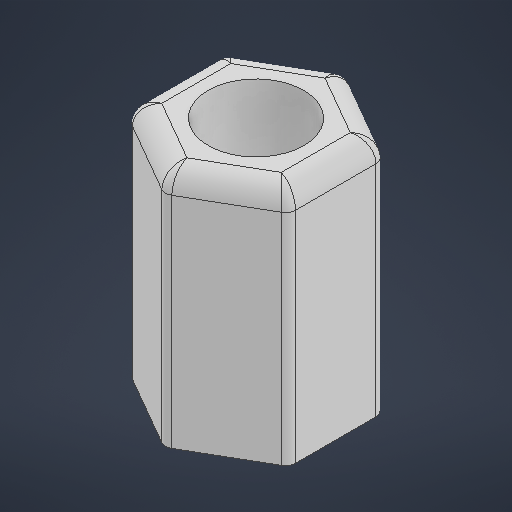
# Autodesk Inventor part: Гайка_М4
Saved by Autodesk Inventor 2026 (Build 300175050, 175E)
## iProperties
Created: 2026-11-05
Part Number: Гайка_М4
Material: Типовые
Document SubType Name: Modeling
Designer: VK7
Density: 1 g/cm^3
Appearance: По умолчанию
Author: VK7
## iProperties of the stored document Гайка_М5_3DПЕЧАТЬ.ipt
Created: 2026-11-05
Part Number: Гайка_М5_3DПЕЧАТЬ
Material: Типовые
Document SubType Name: Modeling
Designer: VK7
Density: 1 g/cm^3
Appearance: По умолчанию
Author: VK7
Autodesk Inventor part; units mm, degrees
ref_plane "YZ Plane" through (0, 0, 0) normal (1, 0, 0) x (0, 1, 0)
ref_plane "XZ Plane" through (0, 0, 0) normal (0, 1, 0) x (-1, 0, 0)
ref_plane "XY Plane" through (0, 0, 0) normal (0, 0, 1) x (1, 0, 0)
sketch "Эскиз1" plane through (0, 0, 0) normal (0, 1, 0) x (-1, 0, 0)
  line L0 (0, 0) -> (4, 0)
  line L1 (4, 0) -> (4, 3)
  line L2 (4, 3) -> (4, -3)
  line L3 (-0.5981, 4.9641) -> (4.5981, 1.9641)
  line L4 (-4.5981, 1.9641) -> (0.5981, 4.9641)
  line L5 (-4, -3) -> (-4, 3)
  line L6 (0.5981, -4.9641) -> (-4.5981, -1.9641)
  line L7 (4.5981, -1.9641) -> (-0.5981, -4.9641)
  circle A0 centre (0, 0) radius 2.4
  point P0 (4, 2.3094)
  point P1 (0, 4.6188)
  point P2 (-4, 2.3094)
  point P3 (-4, -2.3094)
  point P4 (0, -4.6188)
  point P5 (4, -2.3094)
  dimension "d0" = 4
  dimension "d1" = 3
  dimension "d2" = 6
  dimension "d5" = 360
  dimension "d7" = 4.8
  constraints: 16 end point, 1 centre point, 1 coincident, 1 horizontal, 1 perpendicular, 1 point on line, 19 other
  measures "d0" distance of L0.start L0.end
  measures "d1" distance of L0.end L1.end
  measures "d2" distance of L1.end L2.end
  measures "d7" diameter of A0
extrude "Выдавливание1" add sketch "Эскиз1" along normal blind 12
fillet "Сопряжение1" radius 0.5 6 edges at (-4, 6, 2.3094) (0, 6, 4.6188) (4, 6, 2.3094) (4, 6, -2.3094) (0, 6, -4.6188) (-4, 6, -2.3094)
fillet "Сопряжение2" radius 1 13 edges at (-3.933, 12, 2.2707) (-2, 12, 3.4641) (0, 12, 4.5415) (2, 12, 3.4641) (3.933, 12, 2.2707) (4, 12, 0) (3.933, 12, -2.2707) (2, 12, -3.4641) (0, 12, -4.5415) (-2, 12, -3.4641) (-3.933, 12, -2.2707) (-4, 12, 1.0104) (-4, 12, -1.0104)
